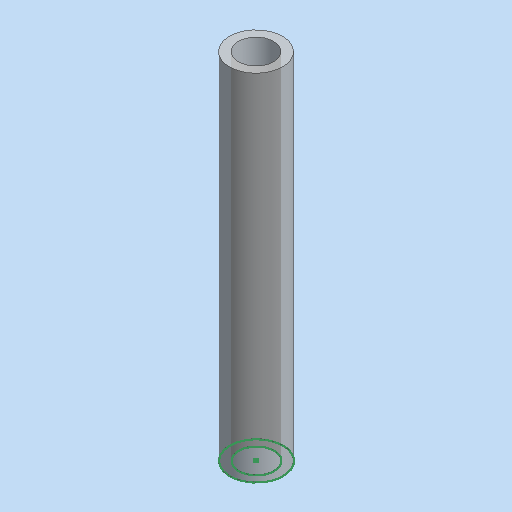
# Autodesk Inventor part: MM0868AN100_G80_541
Saved by Autodesk Inventor 2023.3 (Build 273359000, 359)
## iProperties
Part Number: MM0868AN100_G80_541
Material: Generisch
Catalog Web Link: www.cadenas.de
Description: =<RBPARTNOTITLE2>
Vendor: Perma-Tech
Document SubType Name: Modeling
Designer: partserver
Manufacturer: FESTO
Mass: 435 g
Surface Area: 12.8805 cm^2
Volume: 0.628319 cm^3
Density: 692.324 g/cm^3
Appearance: PSOLRGB-224-224-224
Category: PARTsolutions
Company: FESTO
PSOL_IDENT_0: {$CADENAS_DATA\23d-libs\festo\parts\p\pan\pan_bk.prj},229 {VTYP=3D},{NB=553610 PAN-R-6-NT-25-CB---(2
PSOL_IDENT_1: 5)},{LINA=553610 PAN-R-6-NT-25-CB},{NN=PAN-(BK)},{DATE=19.10.2020 12:51:10},{GEOMDATE=19.10.2020 12:
PSOL_IDENT_2: 50:44},{VERSION=},{LINEID=10},{WBVAR=MA,DA,COL,LT,LEN,P,XLEN},{WBNUMERIC=DA,LEN,XLEN}  {NB=553610 PA
PSOL_IDENT_3: N-R-6-NT-25-CB---(25)},{LINA=553610 PAN-R-6-NT-25-CB},{KT=DUMMY},{TNR=553610},{TYP=PAN},{MA=R},{DA=6
PSOL_IDENT_4: },{DI=4},{COL=NT},{LT=-},{LEN=25},{P=CB},{COLOR=0.88,0.88,0.88,0.30},{COLT=-NT},{PT=-CB},{P1= 'CB'},
PSOL_IDENT_5: {LEN1=25,50,100,200,300,400,500},{MAN=-R},{LTT=},{COL1= 'SI', 'BL', 'SW',  'GE', 'GN', 'RT', 'BR', '
PSOL_IDENT_6: WS', 'NT' },{XLEN=25},{MASSBASIC=0.0174},{CNSMASSEXACT=0.435},{IDCODE=PAN-R-6-NT-25-CB}
NB: 553610 PAN-R-6-NT-25-CB---(25)
NN: PAN-(BK)
NT: Plastic tubing
NBSYN: $TNR. $TYP.$MAN.-$DA.$COLT.$LTT.-$LEN.$PT.---($XLEN.)
LINA: 553610 PAN-R-6-NT-25-CB
CATALOG: Festo
TNR: 553610
TYP: PAN
MA: R
DA: 6
DI: 4
COL: NT
LT: -
LEN: 25
P: CB
XLEN: 25
CNSMASSEXACT: 0.435
SUPPLIER: FESTO
ARTICLENO: 553610 PAN-R-6-NT-25-CB---(25)
BOMINFO: 553610 PAN-R-6-NT-25-CB
CREATOR: CADENAS GmbH
RBDRAWINGMISSINGSPEC: --
RBGBREMARKSINDEX: E
RBPARTNOTITLE1: plastic tube polyamid 12W; l=45mm
AnP_Kategorie: 2
AnP_Material: =<Material>
RBPARTMADEOF: Art.Nr. 101494 (25m)
RBPARTNOTITLE2: Kunststoffschlauch Polyamid 12W; l=45mm
RBMATERIAL: --
RBSURFACE2: Plastic tubing
RBMATNO: =<Part Number>
Title: 553610 PAN-R-6-NT-25-CB
Author: Cadenas PARTsolutions
Comments: =<RBSURFACE2>
Keywords: =<RBPARTMADEOF>
Revision Number: 01
Autodesk Inventor part; units mm, degrees
sketch "Skizze_1" plane through (0, 0, 0) normal (0, 0, 1) x (1, 0, 0)
  circle A0 centre (0, 0) radius 3
  circle A1 centre (0, 0) radius 2
  constraints: 2 centre point
extrude "Extrusion1" add sketch "Skizze_1" against normal blind 80
sketch "Sketch_1" plane through (0, 0, 0) normal (1, 0, 0) x (0, 1, 0)
  line L0 (3, -74) -> (-3, -80)
  line L1 (-3, -80) -> (-3, -86)
  line L2 (-3, -86) -> (3, -86)
  line L3 (3, -86) -> (3, -74)
  constraints: 8 end point
extrude "Extrusion2" cut sketch "Sketch_1" along normal mid plane 6
ref_plane "PAN_XY" through (0, 0, 0) normal (0, 0, 1) x (1, 0, 0)
ref_plane "PAN_YZ" through (0, 0, 0) normal (1, 0, 0) x (0, 1, 0)
ref_plane "PAN_ZX" through (0, 0, 0) normal (0, 1, 0) x (0, 0, 1)
ref_plane "Arbeitsebene4" through (0, 0, -40) normal (0, 0, 1) x (1, 0, 0)
sketch "Skizze3" plane through (0, 0, -40) normal (0, 0, 1) x (1, 0, 0)
  circle A0 centre (0, 0) radius 2 projected
  circle A1 centre (0, 0) radius 3 projected
extrude "Extrusion3" cut sketch "Skizze3" against normal through all
sketch "Skizze4" plane through (0, 0, 0) normal (0, 0, 1) x (1, 0, 0)
  circle A0 centre (0, 0) radius 2 projected
  circle A1 centre (0, 0) radius 3 projected
body "Solid1"
